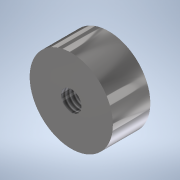
# Autodesk Inventor part: E1018NEO
Saved by Autodesk Inventor 2021.2 (Build 252289000, 289)
## iProperties
Created: 2026-10-13
Part Number: E1018NEO
Material: Magnet
Document SubType Name: Modeling
Designer: nelso
Density: 7.85 g/cm^3
Appearance: Semi-Polished(1)
Author: nelso
Autodesk Inventor part; units mm, degrees
ref_plane "YZ Plane" through (0, 0, 0) normal (1, 0, 0) x (0, 1, 0)
ref_plane "XZ Plane" through (0, 0, 0) normal (0, 1, 0) x (-1, 0, 0)
ref_plane "XY Plane" through (0, 0, 0) normal (0, 0, 1) x (1, 0, 0)
sketch "Sketch1" plane through (0, 0, 0) normal (0, 1, 0) x (-1, 0, 0)
  circle A0 centre (0, 0) radius 5
  dimension "d0" = 10
  constraints: 1 centre point, 1 coincident
  measures "d0" diameter of A0
extrude "Extrusion1" add sketch "Sketch1" along normal mid plane 4.5
sketch "Sketch2" plane through (0, 2.25, 0) normal (0, 1, 0) x (1, 0, 0)
  point P0 (0, 0)
  point P1 (0, 0)
  constraints: 1 coincident
hole "Hole1" at (0, 2.25, 0) direction (0, -1, 0) diameter 2.459 end through all countersink diameter 3.023 countersink angle 82 thread size "M3x0.5" class "6H" standard "ISO Metric profile"
sketch "Sketch3" plane through (0, 2.25, 0) normal (0, 1, 0) x (1, 0, 0)
  circle A0 centre (0, 0) radius 1.7089
  circle A1 centre (0, 0) radius 4.8079
  circle A2 centre (0, 0) radius 4.6644
  circle A3 centre (0, 0) radius 1.8551
  constraints: 4 centre point, 3 coincident
extrude "Extrusion2" cut sketch "Sketch3" against normal blind 0.1
body "Solid1"
